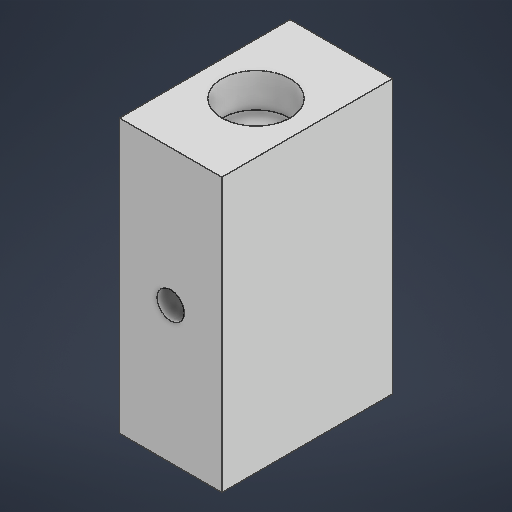
# Autodesk Inventor part: Pieza14
Saved by Autodesk Inventor 2027.1 (Build 311270010, 270A)
## iProperties
Created: 2026-11-02
Part Number: Pieza14
Material: Genérico
Document SubType Name: Modeling
Designer: MANGEL
Density: 1 g/cm^3
Appearance: Valor por defecto
Author: MANGEL
Autodesk Inventor part; units mm, degrees
ref_plane "YZ Plane" through (0, 0, 0) normal (1, 0, 0) x (0, 1, 0)
ref_plane "XZ Plane" through (0, 0, 0) normal (0, 1, 0) x (-1, 0, 0)
ref_plane "XY Plane" through (0, 0, 0) normal (0, 0, 1) x (1, 0, 0)
sketch "Boceto1" plane through (0, 0, 0) normal (1, 0, 0) x (0, 1, 0)
  line L0 (-20, 12.5) -> (20, 12.5)
  line L1 (20, 12.5) -> (20, -12.5)
  line L2 (20, -12.5) -> (-20, -12.5)
  line L3 (-20, -12.5) -> (-20, 12.5)
  line L4 (-20, 12.5) -> (20, -12.5) construction
  line L5 (20, 12.5) -> (-20, -12.5) construction
  point P0 (0, 0)
  dimension "d0" = 25
  dimension "d1" = 40
  constraints: 12 end point, 2 midpoint, 2 parallel, 1 horizontal, 1 perpendicular
  measures "d0" distance of L0.end L1.end
  measures "d1" distance of L1.end L2.end
extrude "Extrusión1" add sketch "Boceto1" along normal blind 15
sketch "Boceto2" plane through (0, -20, 12.5) normal (0, 0, 1) x (1, 0, 0)
  circle A0 centre (7.5, 20) radius 2
  line L0 (15, 40) -> (15, 0) projected
  line L1 (0, 40) -> (15, 40) projected
  point P0 (0, 20)
  point P1 (15, 20)
  point P2 (7.5, 40)
  dimension "d4" = 4
  constraints: 2 midpoint, 1 centre point, 1 horizontal alignment, 1 vertical alignment
  measures "d4" diameter of A0
extrude "Extrusión2" cut sketch "Boceto2" against normal through all
sketch "Boceto3" plane through (0, 20, 12.5) normal (0, 1, 0) x (1, 0, 0)
  circle A0 centre (7.5, 12.5) radius 5
  line L0 (15, 25) -> (15, 0) projected
  line L1 (0, 25) -> (15, 25) projected
  point P0 (0, 12.5)
  point P1 (15, 12.5)
  point P2 (7.5, 25)
  dimension "d7" = 10
  constraints: 2 midpoint, 1 centre point, 1 horizontal alignment, 1 vertical alignment
  measures "d7" diameter of A0
extrude "Extrusión3" cut sketch "Boceto3" against normal blind 5
